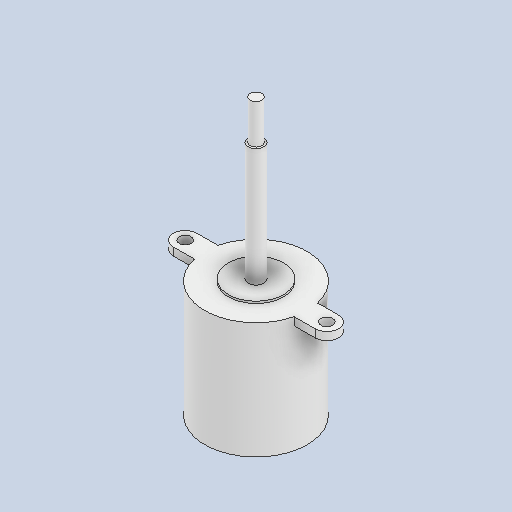
# Autodesk Inventor part: piston_motor
Saved by Autodesk Inventor 2026.1 (Build 301233020, 233B)
## iProperties
Created: 2025-12-09
Part Number: piston_motor
Material: Plastica ABS
Document SubType Name: Modeling
Designer: maxbu
Density: 1.06 g/cm^3
Appearance: Liscia - Bianco
Mass: 17.3184 g
Surface Area: 42.0974 cm^2
Volume: 16.3381 cm^3
Author: maxbu
Autodesk Inventor part; units mm, degrees
ref_plane "YZ Plane" through (0, 0, 0) normal (1, 0, 0) x (0, 1, 0)
ref_plane "XY Plane" through (0, 0, 0) normal (0, 0, 1) x (1, 0, 0)
ref_plane "Piano di lavoro1" through (0, 8, 0) normal (0, 1, 0) x (-1, 0, 0)
sketch "Schizzo2" plane through (0, 0, 0) normal (1, 0, 0) x (0, 1, 0)
  line L0 (10, 0) -> (10, -1.5)
  line L1 (-30, -2) -> (-30, -7)
  line L2 (-30, -7) -> (-30.5, -7)
  line L3 (-30.5, -7) -> (-30.5, -13)
  line L4 (-30.5, -13) -> (-60, -13)
  line L5 (-60, -13) -> (-60, 0)
  line L6 (10, 0) -> (-60, 0)
  line L7 (10, -1.5) -> (0, -1.5)
  line L8 (0, -1.5) -> (0, -2)
  line L9 (0, -2) -> (-30, -2)
  line L10 (0, -1.5) -> (0, 0) construction
  dimension "d13" = 10
  dimension "d15" = 7
  dimension "d16" = 13
  dimension "d17" = 30
  dimension "d18" = 0.5
  dimension "d19" = 30
  dimension "d21" = 1.5
  dimension "d22" = 2
  constraints: 22 end point, 5 perpendicular, 3 horizontal, 2 vertical, 1 point on line
  measures "d13" distance from line of L0 L10.end
  measures "d15" distance between parallel lines of L6 L2
  measures "d16" distance between parallel lines of L6 L4
  measures "d17" distance between parallel lines of L1 L5
  measures "d18" distance of L1.end L2.end
  measures "d19" distance from line of L1 L10.end
  measures "d21" distance between parallel lines of L6 L7
  measures "d22" distance between parallel lines of L6 L9
revolve "Rivoluzione1" add sketch "Schizzo2" angle 360 about axis through (0, 10, 0) along (0, -1, 0)
sketch "Schizzo3" plane through (0, -30.5, 0) normal (0, 1, 0) x (1, 0, 0)
  arc A0 (-18, 3) -> (-18, -3) centre (-18, 0) ccw
  circle A1 centre (-18, 0) radius 1.5
  line L0 (-18, 3) -> (-12.6491, 3)
  circle A2 centre (0, 0) radius 13 projected
  line L1 (-18, -3) -> (-12.6491, -3)
  circle A3 centre (0, 0) radius 2 projected
  line L2 (0, 0) -> (0, 13) construction
  line L3 (-18, 0) -> (0, 0) construction
  arc A4 (18, -3) -> (18, 3) centre (18, 0) ccw
  circle A5 centre (18, 0) radius 1.5
  line L4 (18, 3) -> (12.6491, 3)
  line L5 (18, -3) -> (12.6491, -3)
  line L6 (18, 0) -> (0, 0) construction
  point P0 (0, 0)
  dimension "d23" = 18
  dimension "d24" = 3
  dimension "d25" = 3
  constraints: 14 end point, 7 point on circle, 6 symmetric about line, 4 centre point, 3 horizontal, 2 coincident, 2 tangent, 1 vertical, 2 other
  measures "d23" distance from line of L2 A0.centre
  measures "d24" diameter of A1
  measures "d25" radius of A0
extrude "Estrusione1" add sketch "Schizzo3" against normal blind 2 contours L0 A2 L1 A0 | L4 A4 L5 A2
